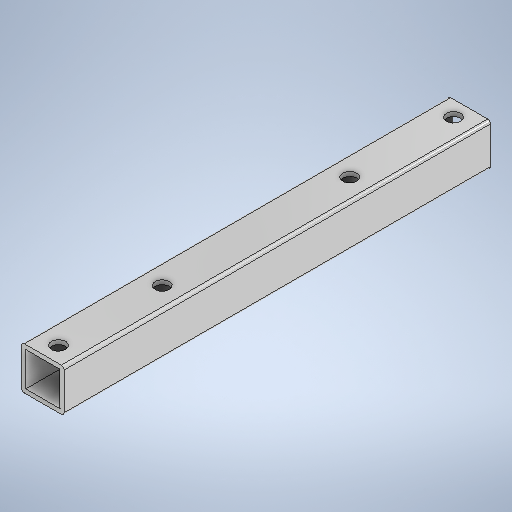
# Autodesk Inventor part: Профиль_алюминиевый
Saved by Autodesk Inventor 2025.1 (Build 291241000, 241)
## iProperties
Created: 2026-10-12
Part Number: Профиль_алюминиевый
Material: Алюминий 6061
Document SubType Name: Modeling
Designer: Ваня
Density: 2.7 g/cm^3
Appearance: Алюминий — полированный
Author: Ваня
Autodesk Inventor part; units mm, degrees
ref_plane "YZ Plane" through (0, 0, 0) normal (1, 0, 0) x (0, 1, 0)
ref_plane "XZ Plane" through (0, 0, 0) normal (0, 1, 0) x (-1, 0, 0)
ref_plane "XY Plane" through (0, 0, 0) normal (0, 0, 1) x (1, 0, 0)
sketch "Эскиз1" plane through (0, 0, 0) normal (0, 0, 1) x (1, 0, 0)
  line L0 (-7.5, 7.5) -> (7.5, 7.5)
  line L1 (7.5, 7.5) -> (7.5, -7.5)
  line L2 (7.5, -7.5) -> (-7.5, -7.5)
  line L3 (-7.5, -7.5) -> (-7.5, 7.5)
  line L4 (-7.5, 7.5) -> (7.5, -7.5) construction
  line L5 (7.5, 7.5) -> (-7.5, -7.5) construction
  line L6 (-6, 6) -> (6, 6)
  line L7 (6, 6) -> (6, -6)
  line L8 (6, -6) -> (-6, -6)
  line L9 (-6, -6) -> (-6, 6)
  line L10 (-6, 6) -> (6, -6) construction
  line L11 (6, 6) -> (-6, -6) construction
  point P0 (0, 0)
  dimension "d0" = 15
  dimension "d1" = 15
  dimension "d2" = 12
  dimension "d3" = 12
  constraints: 24 end point, 4 midpoint, 4 parallel, 2 horizontal, 2 perpendicular
  measures "d0" distance of L1.end L2.end
  measures "d1" distance of L0.end L1.end
  measures "d2" distance of L7.end L8.end
  measures "d3" distance of L6.end L7.end
extrude "Выдавливание1" add sketch "Эскиз1" along normal blind 150
fillet "Сопряжение1" radius 1 4 edges at (-7.5, 7.5, 75) (7.5, 7.5, 75) (-7.5, -7.5, 75) (7.5, -7.5, 75)
sketch "Эскиз2" plane through (-6.5, 7.5, 0) normal (0, 1, 0) x (1, 0, 0)
  line L0 (6.5, 0) -> (6.5, -3)
  line L1 (6.5, -3) -> (6.5, -5.5)
  circle A0 centre (6.5, -5.5) radius 2.5
  line L2 (6.5, -5.5) -> (6.5, -42)
  circle A1 centre (6.5, -42) radius 2.5
  dimension "d7" = 3
  dimension "d8" = 2.5
  dimension "d9" = 36.5
  dimension "d10" = 5
  constraints: 6 end point, 3 vertical, 2 coincident, 1 centre point, 1 vertical alignment, 2 other
  measures "d7" distance of L0.start L0.end
  measures "d8" distance of L0.end L1.end
  measures "d9" distance of L2.start L2.end
  measures "d10" diameter of A1
extrude "Выдавливание2" cut sketch "Эскиз2" against normal blind 5
sketch "Эскиз3" plane through (-6.5, 7.5, 0) normal (0, 1, 0) x (1, 0, 0)
  line L0 (0.5, -150) -> (12.5, -150) projected
  line L1 (6.5, -150) -> (6.5, -144.5)
  circle A0 centre (6.5, -144.5) radius 2.5
  line L2 (6.5, -144.5) -> (6.5, -108)
  circle A1 centre (6.5, -108) radius 2.5
  point P0 (6.5, 0)
  dimension "d13" = 5.5
  dimension "d14" = 5
  dimension "d15" = 36.5
  dimension "d16" = 5
  constraints: 4 end point, 2 centre point, 2 coincident, 2 vertical, 1 midpoint
  measures "d13" distance of L1.start L1.end
  measures "d14" diameter of A0
  measures "d15" distance of L2.start L2.end
  measures "d16" diameter of A1
extrude "Выдавливание3" cut sketch "Эскиз3" against normal blind 5
